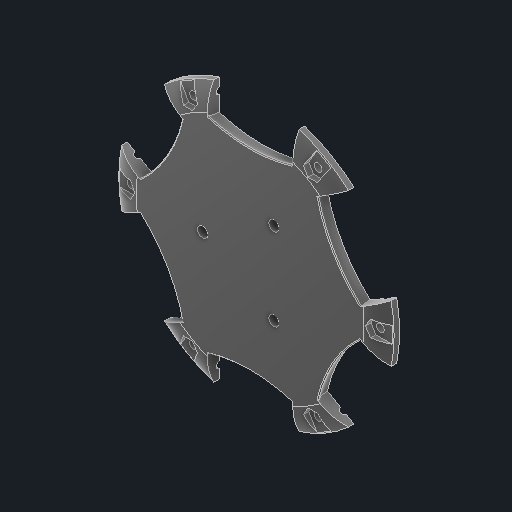
# Autodesk Inventor part: Tampa roda (porca - trás)
Saved by Autodesk Inventor 2026.1 (Build 301233000, 233)
## iProperties
Created: 2025-01-03
Part Number: Tampa roda (porca - trás)
Material: ABS plástico
Document SubType Name: Modeling
Designer: Cliente
Density: 0.914875 g/cm^3
Appearance: Suave - Preto
Mass: 30.4 g
Surface Area: 167.338 cm^2
Volume: 33.2286 cm^3
Author: Cliente
Autodesk Inventor part; units mm, degrees
ref_plane "YZ Plane" through (0, 0, 0) normal (1, 0, 0) x (0, 1, 0)
ref_plane "XZ Plane" through (0, 0, 0) normal (0, 1, 0) x (-1, 0, 0)
ref_plane "XY Plane" through (0, 0, 0) normal (0, 0, 1) x (1, 0, 0)
sketch "Esboço1" plane through (0, 0, 0) normal (0, 0, 1) x (1, 0, 0)
  circle A0 centre (0, 0) radius 58
  line L0 (0, 0) -> (-52.5, 0)
  circle A1 centre (-52.5, 0) radius 1.65
  arc A2 (17.5, 57.3912) -> (-17.5, 57.3912) centre (0, 0) ccw
  line L1 (0, 0) -> (0, 50)
  line L2 (-17.5, 50) -> (17.5, 50)
  line L3 (-17.5, 50) -> (-17.5, 57.3912)
  line L4 (17.5, 50) -> (17.5, 57.3912)
  arc A3 (-17.5, 42.6088) -> (17.5, 42.6088) centre (0, 100) ccw
  line L5 (-17.5, 50) -> (-17.5, 42.6088)
  line L6 (17.5, 50) -> (17.5, 42.6088)
  line L7 (18, 50) -> (18, 42.2397)
  arc A4 (-18, 42.2397) -> (18, 42.2397) centre (0, 100) ccw
  line L8 (-18, 42.2397) -> (-18, 50)
  line L9 (-18, 50) -> (-18, 57.7603)
  arc A5 (18, 57.7603) -> (-18, 57.7603) centre (0, 0) ccw
  line L10 (18, 57.7603) -> (18, 50)
  circle A6 centre (-26.25, -45.4663) radius 1.65
  line L11 (-52.3013, 9.4115) -> (-59.0219, 13.2917)
  line L12 (-45.5807, 5.5314) -> (-52.3013, 9.4115)
  arc A7 (-45.5807, 5.5314) -> (-27.5807, 36.7083) centre (-86.6025, 50) ccw
  line L13 (-34.3013, 40.5885) -> (-27.5807, 36.7083)
  line L14 (-41.0219, 44.4686) -> (-34.3013, 40.5885)
  circle A8 centre (26.25, -45.4663) radius 1.65
  line L15 (-34.3013, -40.5885) -> (-41.0219, -44.4686)
  line L16 (-27.5807, -36.7083) -> (-34.3013, -40.5885)
  arc A9 (-27.5807, -36.7083) -> (-45.5807, -5.5314) centre (-86.6025, -50) ccw
  line L17 (-52.3013, -9.4115) -> (-45.5807, -5.5314)
  line L18 (-59.0219, -13.2917) -> (-52.3013, -9.4115)
  circle A10 centre (52.5, 0) radius 1.65
  line L19 (18, -50) -> (18, -57.7603)
  line L20 (18, -42.2397) -> (18, -50)
  arc A11 (18, -42.2397) -> (-18, -42.2397) centre (0, -100) ccw
  line L21 (-18, -50) -> (-18, -42.2397)
  line L22 (-18, -57.7603) -> (-18, -50)
  circle A12 centre (26.25, 45.4663) radius 1.65
  line L23 (52.3013, -9.4115) -> (59.0219, -13.2917)
  line L24 (45.5807, -5.5314) -> (52.3013, -9.4115)
  arc A13 (45.5807, -5.5314) -> (27.5807, -36.7083) centre (86.6025, -50) ccw
  line L25 (34.3013, -40.5885) -> (27.5807, -36.7083)
  line L26 (41.0219, -44.4686) -> (34.3013, -40.5885)
  circle A14 centre (-26.25, 45.4663) radius 1.65
  line L27 (34.3013, 40.5885) -> (41.0219, 44.4686)
  line L28 (27.5807, 36.7083) -> (34.3013, 40.5885)
  arc A15 (27.5807, 36.7083) -> (45.5807, 5.5314) centre (86.6025, 50) ccw
  line L29 (52.3013, 9.4115) -> (45.5807, 5.5314)
  line L30 (59.0219, 13.2917) -> (52.3013, 9.4115)
  line L31 (0, 0) -> (0, 20)
  circle A16 centre (0, 20) radius 2.15
  circle A17 centre (-17.3205, -10) radius 2.15
  circle A18 centre (17.3205, -10) radius 2.15
  line L32 (0, 0) -> (-20, 0)
  circle A19 centre (-20, 0) radius 2.15
  circle A20 centre (10, -17.3205) radius 2.15
  circle A21 centre (10, 17.3205) radius 2.15
  point P0 (-18, 55.1362)
  point P1 (-38.7493, 43.1566)
  point P2 (-56.7493, 11.9796)
  point P3 (-56.7493, -11.9796)
  point P4 (-38.7493, -43.1566)
  point P5 (-18, -55.1362)
  point P6 (18, -55.1362)
  point P7 (38.7493, -43.1566)
  point P8 (56.7493, -11.9796)
  point P9 (56.7493, 11.9796)
  point P10 (38.7493, 43.1566)
  point P11 (18, 55.1362)
  dimension "d0" = 116
  dimension "d1" = 52.5
  dimension "d2" = 3.3
  dimension "d3" = 120
  dimension "d4" = 50
  dimension "d5" = 35
  dimension "d6" = 0.5
  dimension "d7" = 0.5
  dimension "d10" = 360
  dimension "d12" = 20
  dimension "d13" = 4.3
  dimension "d16" = 360
  dimension "d44" = 20
  dimension "d45" = 4.3
  dimension "d48" = 360
  constraints: 66 end point, 22 centre point, 18 point on circle, 5 coincident, 3 symmetric about line, 2 horizontal, 2 parallel, 2 point on line, 2 vertical, 1 midpoint, 116 other
  measures "d0" diameter of A0
  measures "d1" distance of L0.start L0.end
  measures "d2" diameter of A1
  measures "d3" diameter of A2
  measures "d4" distance of L1.end L1.start
  measures "d5" distance of L2.start L2.end
  measures "d6" radial gap between concentric circles of A3 A4
  measures "d7" distance between parallel lines of L3 L9
  measures "d12" distance of L1.start L31.end
  measures "d13" diameter of A16
  measures "d44" distance of L1.start L32.end
  measures "d45" diameter of A19
extrude "Extrusão1" add sketch "Esboço1" along normal blind 5 contours A0 L23 L24 A13 L25 L26 L19 L20 A11 L21 L22 L15 L16 A9 L17 L18 L11 L12 A7 L13 L14 L9 L8 A4 L7 L10 L27 L28 A15 L29 L30 | A16 L1 | L1 A16 | A17 | A18
sketch "Esboço2" plane through (0, 0, 0) normal (1, 0, 0) x (0, 1, 0)
  line L0 (0, 0) -> (50, 0)
  line L1 (42.2397, 0) -> (55.1362, 0) projected
  line L2 (39.5, 5) -> (39.5, 0) projected
  circle A0 centre (50, 0) radius 10.5
  line L3 (39.5, 5) -> (42.2397, 5) projected
  line L4 (39.5, 5) -> (40.2, 5)
  line L5 (40.2, 5) -> (40.574, 4.626)
  circle A1 centre (50, 0) radius 1.35
  point P0 (40.7669, 5)
  dimension "d20" = 50
  dimension "d23" = 0.7
  dimension "d24" = 135
  dimension "d25" = 2.7
  constraints: 6 end point, 2 centre point, 2 coincident, 2 point on circle, 2 point on line
  measures "d20" distance of L0.start L0.end
  measures "d23" distance of L2.start L4.end
  measures "d24" angle of L4 L5
  measures "d25" diameter of A1
sketch3d "Esboço 3D1"
sketch3d "Esboço 3D2"
  arc A0 (-18, 42.2397, 5) -> (18, 42.2397, 5) centre (0, 100, 5) ccw
sweep "Varredura1" add profiles "Esboço2" path "Esboço 3D2" keep normal constant yes contours L3 L5 A0 L2
extrude "Extrusão2" cut sketch "Esboço2" along normal mid plane 42.3 contours A1 L1 L0 | L0 L1 A1
sketch "Esboço3" plane through (0, 0, 0) normal (0, 1, 0) x (-1, 0, 0)
  line L0 (58, 0) -> (58, 5) projected
  line L1 (58, 5) -> (48, 5)
  line L2 (56.7493, 5) -> (45.5807, 5) projected
  line L3 (48, 5) -> (48, -15)
  circle A0 centre (48, -15) radius 20
  line L4 (0, -43) -> (0, 13) projected
  point P0 (0, 0)
  point P1 (58, 2.3205)
  dimension "d28" = 10
  dimension "d29" = 20
  constraints: 4 end point, 1 coincident, 1 point on line, 1 vertical, 3 other
  measures "d28" distance of L0.end L1.end
  measures "d29" distance of L1.end L3.end
revolve "Revolução1" cut sketch "Esboço3" angle 360 about axis through (0, 0, -10) along (0, 0, 1) contours A0 L1 L0
pattern_circular "Padrão circular1" count 6 over 360 about axis through (0, 0, -10) along (0, 0, 1) of "Varredura1", "Extrusão2"
sketch "Esboço4" plane through (0, 0, 5) normal (0, 0, 1) x (1, 0, 0)
  circle A0 centre (0, 0) radius 30
  dimension "d34" = 60
  constraints: 1 centre point, 1 coincident
  measures "d34" diameter of A0
extrude "Extrusão3" [suppressed]
sketch "Esboço5" plane through (0, 0, 5) normal (0, 0, 1) x (1, 0, 0)
  circle A0 centre (-52.5, 0) radius 1.65 projected
  arc A1 (-56.7493, 11.9796) -> (-56.7493, -11.9796) centre (0, 0) ccw projected
  line L0 (-48.7472, 0) -> (-50.6236, -3.25)
  line L1 (-50.6236, -3.25) -> (-54.3764, -3.25)
  line L2 (-54.3764, -3.25) -> (-56.2528, 0)
  line L3 (-56.2528, 0) -> (-54.3764, 3.25)
  line L4 (-54.3764, 3.25) -> (-50.6236, 3.25)
  line L5 (-50.6236, 3.25) -> (-48.7472, 0)
  line L6 (-48.574, 0) -> (-50.537, -3.4)
  line L7 (-50.537, -3.4) -> (-54.463, -3.4)
  line L8 (-54.463, -3.4) -> (-56.426, 0)
  line L9 (-56.426, 0) -> (-54.463, 3.4)
  line L10 (-54.463, 3.4) -> (-50.537, 3.4)
  line L11 (-50.537, 3.4) -> (-48.574, 0)
  line L12 (-54.463, 3.4) -> (-57.9003, 3.4)
  line L13 (-54.463, -3.4) -> (-57.9003, -3.4)
  dimension "d50" = 6.5
  dimension "d51" = 0.15
  constraints: 28 end point, 2 horizontal, 2 point on circle, 1 coincident, 1 parallel, 18 other
  measures "d50" distance between parallel lines of L1 L4
  measures "d51" distance between parallel lines of L5 L11
extrude "Extrusão4" cut sketch "Esboço5" against normal blind 2.4 contours A0 | L12 L9 L8 L13 A1 | L10 L11 L6 L7 L8 L9 | L0 L1 L2 L3 L4 L5
pattern_circular "Padrão circular2" count 6 over 360 about axis through (0, 0, -10) along (0, 0, 1) of "Extrusão4"
